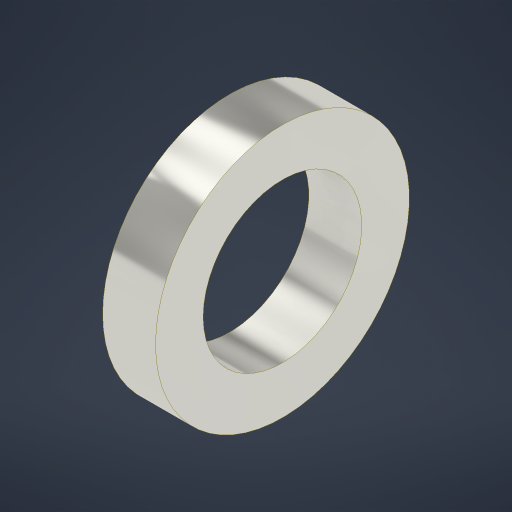
# Autodesk Inventor part: 6802ZZ_61802
Saved by Autodesk Inventor 2023 (Build 270158000, 158)
## iProperties
Created: 2026-11-12
Part Number: 6802ZZ_61802
Material: Steel
Document SubType Name: Modeling
Designer: szykr
Density: 7.85 g/cm^3
Appearance: Silver
Author: szykr
Autodesk Inventor part; units mm, degrees
ref_plane "YZ Plane" through (0, 0, 0) normal (1, 0, 0) x (0, 1, 0)
ref_plane "XZ Plane" through (0, 0, 0) normal (0, 1, 0) x (-1, 0, 0)
ref_plane "XY Plane" through (0, 0, 0) normal (0, 0, 1) x (1, 0, 0)
sketch "Sketch1" plane through (0, 0, 0) normal (0, 1, 0) x (-1, 0, 0)
  line L0 (0, 0) -> (39.3934, 0)
  line L1 (0, 7.5) -> (5, 7.5)
  line L2 (5, 7.5) -> (5, 12)
  line L3 (5, 12) -> (0, 12)
  line L4 (0, 12) -> (0, 7.5)
  dimension "d0" = 24
  dimension "d1" = 15
  dimension "d2" = 5
  constraints: 10 end point, 3 perpendicular, 2 horizontal, 1 vertical alignment
  measures "d0" diameter of L3 L0
  measures "d1" diameter of L1 L0
  measures "d2" distance between parallel lines of L4 L2
revolve "Revolution1" add sketch "Sketch1" angle 360 about axis through (0, 0, 0) along (-1, 0, 0)
body "Solid1"
